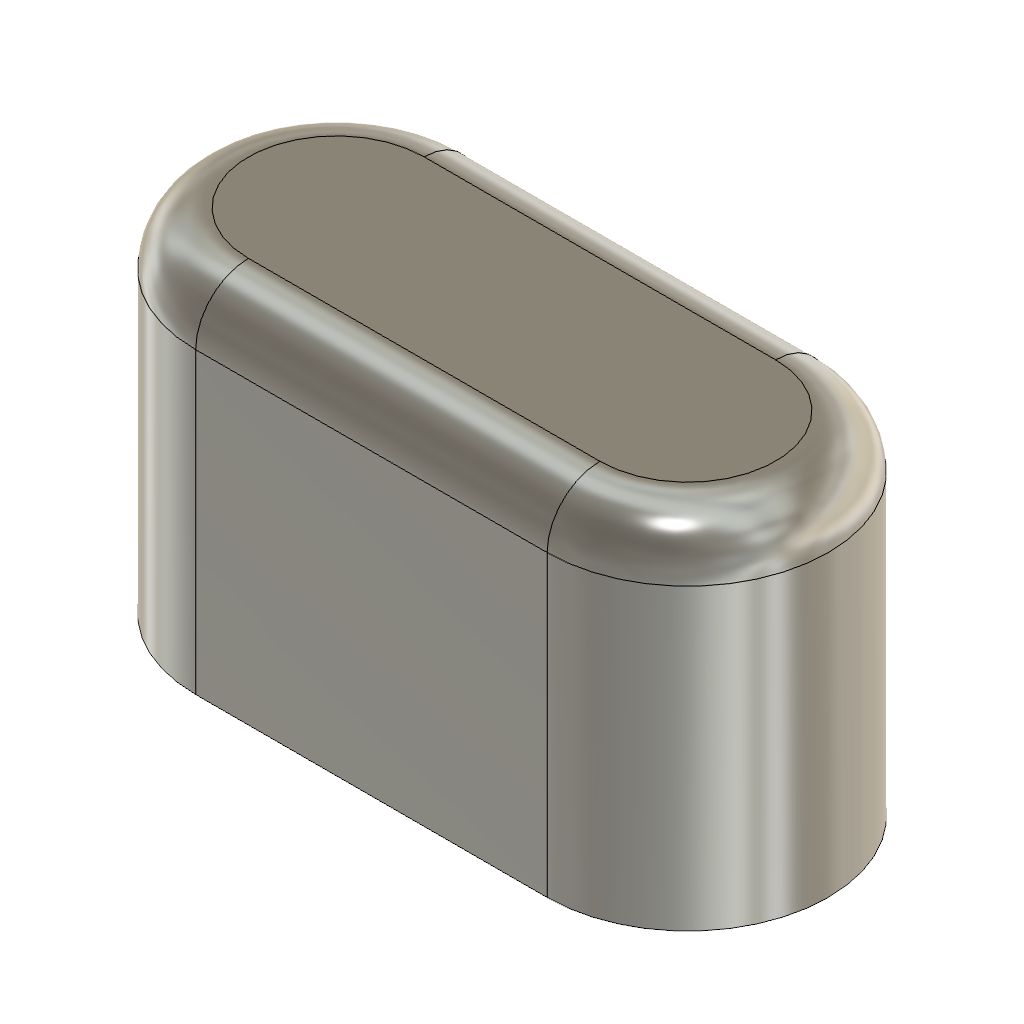
vendor_RoundSlotRim (Autodesk Fusion 360 design; units mm, degrees)
Autodesk Fusion 360 part; units mm, degrees
sketch "Slot sketch" plane through (0, 0, 0) normal (0, 0, 1) x (1, 0, 0)
  line L0 (10, 7) -> (30, 7)
  arc A0 (30, 7) -> (30, 23) centre (30, 15) ccw
  line L1 (30, 23) -> (10, 23)
  arc A1 (10, 23) -> (10, 7) centre (10, 15) ccw
extrude "Slot extrude" add sketch "Slot sketch" along normal blind 20
fillet "Slot round" radius 3 4 edges at (20, 7, 20) (38, 15, 20) (20, 23, 20) (2, 15, 20)
equation "height = 20.0 mm"
